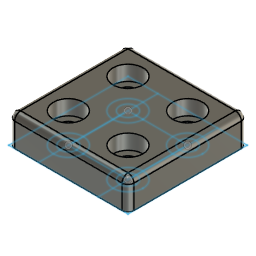
4020_connector (Autodesk Fusion 360 design; units mm, degrees)
part number: 2026-10-17-12-51-00-128
Autodesk Fusion 360 part; units mm, degrees
sketch "Sketch1" plane through (0, 0, 0) normal (0, 0, 1) x (1, 0, 0)
  line L0 (-2.2531, 32.7186) -> (37.7469, 32.7186)
  line L1 (37.7469, 32.7186) -> (37.7469, -7.2814)
  line L2 (37.7469, -7.2814) -> (-2.2531, -7.2814)
  line L3 (-2.2531, -7.2814) -> (-2.2531, 32.7186)
  line L4 (7.7469, 32.7186) -> (7.7469, -7.2814)
  line L5 (27.7469, 32.7186) -> (27.7469, -7.2814)
  circle A0 centre (7.7469, 22.7186) radius 2.75
  circle A1 centre (27.7469, 22.7186) radius 2.75
  circle A2 centre (7.7469, 2.7186) radius 2.75
  circle A3 centre (27.7469, 2.7186) radius 2.75
  line L6 (7.7469, 22.7186) -> (27.7469, 22.7186)
  line L7 (27.7469, 22.7186) -> (27.7469, 2.7186)
  line L8 (27.7469, 2.7186) -> (7.7469, 2.7186)
  line L9 (7.7469, 2.7186) -> (7.7469, 22.7186)
  circle A4 centre (7.7469, 22.7186) radius 5
  circle A5 centre (27.7469, 22.7186) radius 5
  circle A6 centre (7.7469, 2.7186) radius 5
  circle A7 centre (27.7469, 2.7186) radius 5
  dimension "d1" = 10
  dimension "d2" = 20
  dimension "d3" = 10
  dimension "d5" = 5.5
  dimension "d6" = 10
  dimension "d7" = 10
  dimension "d8" = 10
  dimension "d9" = 20
  constraint horizontal L0
  constraint vertical L1
  constraint horizontal L2
  constraint vertical L3
  constraint coincident L0 L4.start
  constraint coincident L2 L4.end
  constraint perpendicular L2 L4
  constraint coincident L0 L5.start
  constraint coincident L2 L5.end
  constraint perpendicular L2 L5
  constraint coincident L4 A0.centre
  constraint coincident L5 A1.centre
  constraint coincident L4 A2.centre
  constraint coincident L5 A3.centre
  constraint horizontal L6
  constraint vertical L7
  constraint horizontal L8
  constraint vertical L9
  constraint coincident A3.centre L7.end
  constraint coincident A0.centre L6.start
  constraint coincident A2.centre L8.end
  constraint coincident A1.centre L6.end
  constraint equal A0 A1
  constraint equal A1 A3
  constraint equal A2 A3
  constraint concentric A0 A4
  constraint concentric A1 A5
  constraint concentric A2 A6
  constraint concentric A3 A7
  constraint equal A4 A6
  constraint equal A4 A5
  constraint equal A5 A7
  measures "d1" distance of L0.start L4.start
  measures "d2" distance of L4.start L5.start
  measures "d3" distance of L0.end L5.start
  measures "d5" diameter of A0
  measures "d6" diameter of A4
  measures "d7" distance of L2 A3.centre
  measures "d8" distance of L0 A1.centre
  measures "d9" distance of A1.centre A3.centre
extrude "Extrude1" add sketch "Sketch1" along normal blind 5 contours L0 L2 L3 L4 L9 A4 A6 | L0 L4 L5 L6 A4 A5 | L0 L1 L2 L5 L7 A5 A7 | L4 A0 L6 A4 | L4 A0 L9 A4 | L2 L4 L5 L8 A6 A7 | L5 A1 L7 A5 | L5 A1 L6 A5 | L4 A0 L6 L9 A4 | L4 L5 L6 L7 L8 L9 A4 A5 A6 A7 | L4 A2 L9 A6 | L4 A2 L8 A6 | L5 A1 L6 L7 A5 | L4 A2 L8 L9 A6 | L5 A3 L8 A7 | L5 A3 L7 A7 | L5 A3 L7 L8 A7
extrude "Extrude2" add sketch "Sketch1" along normal blind 5 from surface at 5 contours L0 L2 L3 L4 L9 A4 A6 | L0 L4 L5 L6 A4 A5 | L0 L1 L2 L5 L7 A5 A7 | L2 L4 L5 L8 A6 A7 | L4 L5 L6 L7 L8 L9 A4 A5 A6 A7
fillet "Fillet1" radius 2 8 edges at (-2.2531, -7.2814, 5) (37.7469, 32.7186, 5) (-2.2531, 32.7186, 5) (-2.2531, 12.7186, 10) (17.7469, 32.7186, 10) (37.7469, 12.7186, 10) (17.7469, -7.2814, 10) (37.7469, -7.2814, 5)
equation "d3 = d1"
